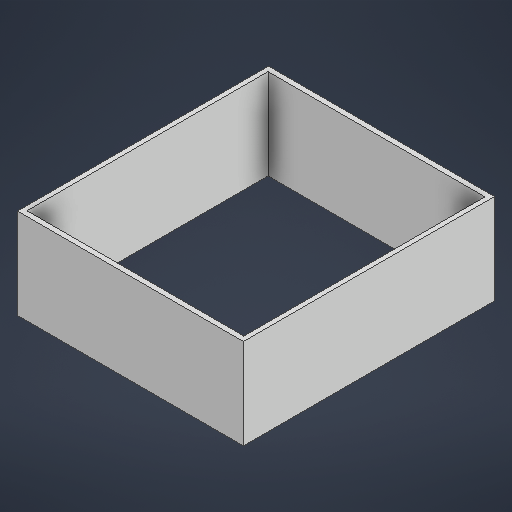
# Autodesk Inventor part: Enclosure Box
Saved by Autodesk Inventor 2026.2 (Build 302298010, 298A)
## iProperties
Created: 2026-03-26
Part Number: Enclosure Box
Material: Generic
Document SubType Name: Modeling
Designer: User
Density: 1 g/cm^3
Appearance: Default
Author: User
Autodesk Inventor part; units mm, degrees
ref_plane "YZ Plane" through (0, 0, 0) normal (1, 0, 0) x (0, 1, 0)
ref_plane "XZ Plane" through (0, 0, 0) normal (0, 1, 0) x (-1, 0, 0)
ref_plane "XY Plane" through (0, 0, 0) normal (0, 0, 1) x (1, 0, 0)
sketch "Sketch1" plane through (0, 0, 0) normal (0, 1, 0) x (-1, 0, 0)
  line L0 (225, 250) -> (-225, 250)
  line L1 (-225, 250) -> (-225, -250)
  line L2 (-225, -250) -> (225, -250)
  line L3 (225, -250) -> (225, 250)
  line L4 (225, 250) -> (-225, -250) construction
  line L5 (-225, 250) -> (225, -250) construction
  line L6 (216, 240) -> (-216, 240)
  line L7 (-216, 240) -> (-216, -240)
  line L8 (-216, -240) -> (216, -240)
  line L9 (216, -240) -> (216, 240)
  line L10 (216, 240) -> (-216, -240) construction
  line L11 (-216, 240) -> (216, -240) construction
  line L12 (147.8259, -240) -> (147.8259, -250)
  point P0 (0, 0)
  dimension "d0" = 450
  dimension "d1" = 500
  dimension "d23" = 10
  constraints: 26 end point, 4 midpoint, 4 parallel, 3 perpendicular, 3 point on line, 2 horizontal
  measures "d0" distance of L2.end L1.end
  measures "d1" distance of L2.end L0.start
  measures "d23" distance of L12.start L12.end
extrude "Extrusion1" add sketch "Sketch1" along normal blind 180
body "Solid1"
